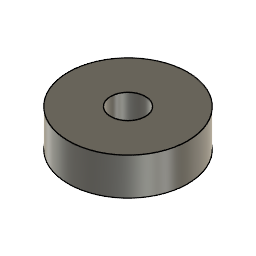
Wheel Assembly Front Side (Autodesk Fusion 360 archive; units mm, degrees)
design "Front Wheel"
Autodesk Fusion 360 part; units mm, degrees
sketch "Sketch1" plane through (0, 0, 0) normal (0, 0, 1) x (1, 0, 0)
  circle A0 centre (0, 0) radius 15.24
  circle A1 centre (0, 0) radius 4.445
  dimension "d1" = 8.89
  dimension "d2" = 30.48
  constraint coincident A0.centre A1.centre
  measures "d1" diameter of A1
  measures "d2" diameter of A0
extrude "Extrude1" add sketch "Sketch1" along normal blind 9.525
equation "d3 = ( 3 / 8 ) * 1 in"

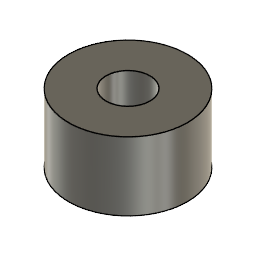
design "Shaft Collar"
Autodesk Fusion 360 part; units mm, degrees
sketch "Sketch1" plane through (0, 0, 0) normal (0, 0, 1) x (1, 0, 0)
  circle A0 centre (0, 0) radius 5.4991
  circle A1 centre (0, 0) radius 2.032
  dimension "d1" = 10.9982
  dimension "d2" = 4.064
  constraint coincident A0.centre A1.centre
  constraint concentric A0 A1
  measures "d1" diameter of A0
  measures "d2" diameter of A1
extrude "Extrude1" add sketch "Sketch1" along normal blind 6.35

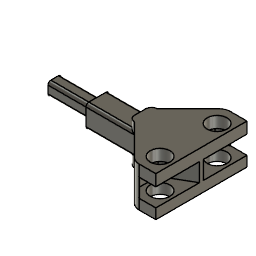
design "Wheel mount"
Autodesk Fusion 360 part; units mm, degrees
sketch "Sketch1" plane through (0, 0, 0) normal (0, 0, 1) x (1, 0, 0)
  line L0 (1.27, -2.54) -> (8.89, -2.54)
  line L1 (8.89, -2.54) -> (8.89, 2.54)
  line L2 (8.89, 2.54) -> (1.27, 2.54)
  line L3 (0, 1.27) -> (0, -1.27)
  line L4 (16.51, 10.16) -> (16.51, -10.16)
  line L5 (8.89, -10.16) -> (8.89, 10.16)
  arc A0 (1.27, 2.54) -> (0, 1.27) centre (1.27, 1.27) ccw
  arc A1 (0, -1.27) -> (1.27, -2.54) centre (1.27, -1.27) ccw
  circle A2 centre (10.795, 6.35) radius 2.2
  circle A3 centre (10.795, -6.35) radius 2.2
  line L6 (9.9421, 10.16) -> (16.51, 10.16)
  line L7 (9.9421, -10.16) -> (16.51, -10.16)
  line L8 (1.27, -2.54) -> (8.1461, -9.4161)
  line L9 (1.27, 2.54) -> (8.1461, 9.4161)
  arc A4 (9.9421, 10.16) -> (8.1461, 9.4161) centre (9.9421, 7.62) ccw
  arc A5 (8.1461, -9.4161) -> (9.9421, -10.16) centre (9.9421, -7.62) ccw
  line L10 (13.6525, 10.16) -> (13.6525, -10.16)
  dimension "d1" = 1.27
  dimension "d2" = 1.27
  dimension "d5" = 4.4
  dimension "d6" = 4.4
  dimension "d8" = 20.32
  dimension "d9" = 7.62
  dimension "d10" = 1.905
  dimension "d13" = 2.54
  dimension "d14" = 20.32
  dimension "d15" = 2.54
  dimension "d16" = 2.54
  dimension "d17" = 45
  dimension "d18" = 12.7
  dimension "d19" = 6.35
  dimension "d31" = 2.8575
  constraint horizontal L0
  constraint vertical L1
  constraint horizontal L2
  constraint vertical L3
  constraint vertical L4
  constraint vertical L5
  constraint midpoint L1 L5
  constraint tangent L2 A0
  constraint tangent L3 A0
  constraint tangent L0 A1
  constraint tangent L3 A1
  constraint midpoint origin L3
  constraint perpendicular L4 L6
  constraint coincident L5.end L9
  constraint coincident L5.end L6
  constraint tangent L9 A4
  constraint tangent L6 A4
  constraint coincident L5.start L8
  constraint coincident L5.start L7
  constraint tangent L8 A5
  constraint tangent L7 A5
  constraint vertical A2.centre A3.centre
  constraint coincident L6 L10.start
  constraint coincident L7 L10.end
  constraint perpendicular L7 L10
  measures "d1" radius of A0
  measures "d2" radius of A1
  measures "d5" diameter of A2
  measures "d6" diameter of A3
  measures "d8" distance of L4.start L4.end
  measures "d9" distance of L4 L5
  measures "d10" distance of L5 A3.centre
  measures "d13" distance of L3.start L3.end
  measures "d14" distance of L5.end L5.start
  measures "d15" radius of A4
  measures "d16" radius of A5
  measures "d17" angle of L0 L8
  measures "d18" vertical distance of A2.centre A3.centre
  measures "d19" vertical distance of origin A2.centre
  measures "d31" distance of A3.centre L10
extrude "Extrude1" add sketch "Sketch1" along normal blind 6.35 contours L0 L1 L2 L3 L5 A0 A1 | L0 L5 A3 L8 A5 | L1 L5 A2 A3 L6 L7 A4 A5 L10 | L2 L5 A2 L9 A4
sketch "Sketch3" plane through (13.6525, 0, 0) normal (1, 0, 0) x (0, 1, 0)
  line L0 (-10.16, 0) -> (10.16, 0)
  line L1 (10.16, 0) -> (10.16, 6.35)
  line L2 (10.16, 6.35) -> (-10.16, 6.35)
  line L3 (-10.16, 6.35) -> (-10.16, 0)
  line L4 (3.81, 5.08) -> (8.89, 5.08)
  line L5 (8.89, 5.08) -> (8.89, 1.27)
  line L6 (8.89, 1.27) -> (3.81, 1.27)
  line L7 (3.81, 1.27) -> (3.81, 5.08)
  line L8 (-10.16, 0) -> (10.16, 0)
  line L9 (10.16, 0) -> (10.16, 6.35)
  line L10 (10.16, 6.35) -> (-10.16, 6.35)
  line L11 (-10.16, 6.35) -> (-10.16, 0)
  line L12 (-8.89, 5.08) -> (-3.81, 5.08)
  line L13 (-3.81, 5.08) -> (-3.81, 1.27)
  line L14 (-3.81, 1.27) -> (-8.89, 1.27)
  line L15 (-8.89, 1.27) -> (-8.89, 5.08)
  dimension "d25" = 3.81
  dimension "d26" = 5.08
  dimension "d27" = 1.27
  dimension "d28" = 1.27
  dimension "d32" = 5.08
  dimension "d33" = 1.27
  dimension "d34" = 1.27
  dimension "d35" = 3.81
  constraint horizontal L4
  constraint vertical L5
  constraint horizontal L6
  constraint vertical L7
  constraint horizontal L12
  constraint vertical L13
  constraint horizontal L14
  constraint vertical L15
  measures "d25" distance of L4.end L5.end
  measures "d26" distance of L4.start L4.end
  measures "d27" distance of L1 L5
  measures "d28" distance of L0 L6
  measures "d32" distance of L12.start L12.end
  measures "d33" distance of L3 L15
  measures "d34" distance of L0 L14
  measures "d35" distance of L12.end L13.end
extrude "Extrude3" cut sketch "Sketch3" against normal blind 5.842 contours L4 L5 L6 L7 | L12 L13 L14 L15
sketch "Sketch2" plane through (0, 0, 0) normal (-1, 0, 0) x (0, -1, 0)
  line L0 (-1.27, 0) -> (1.27, 0)
  line L1 (1.27, 0) -> (1.27, 6.35)
  line L2 (1.27, 6.35) -> (-1.27, 6.35)
  line L3 (-1.27, 6.35) -> (-1.27, 0)
  line L4 (2.54, 5.715) -> (-2.54, 5.715)
  line L5 (-2.54, 5.715) -> (-2.54, 0.635)
  line L6 (-2.54, 0.635) -> (2.54, 0.635)
  line L7 (2.54, 0.635) -> (2.54, 5.715)
  line L8 (2.54, 5.715) -> (-2.54, 0.635) construction
  line L9 (-2.54, 5.715) -> (2.54, 0.635) construction
  point P0 (0, 3.175)
  dimension "d20" = 5.08
  dimension "d21" = 5.08
  dimension "d22" = 3.175
  constraint horizontal L4
  constraint perpendicular L4 L5
  constraint parallel L4 L6
  constraint parallel L5 L7
  constraint coincident L8 P0
  constraint coincident L9 P0
  constraint vertical origin P0
  measures "d20" distance of L4.end L5.end
  measures "d21" distance of L5.end L6.end
  measures "d22" vertical distance of origin P0
extrude "Extrude2" add sketch "Sketch2" along normal blind 19.05 contours L3 L4 L5 L6 | L1 L3 L4 L6 | L1 L4 L6 L7
draft "Draft1" angle 30 neutral plane through (7.8105, 0, 0) pull (1, 0, 0) 1 faces at (11.7052, -8.89, 2.54)
draft "Draft2" angle 30 neutral plane through (7.8105, 0, 0) pull (1, 0, 0) 1 faces at (11.7052, -3.81, 3.81)
draft "Draft3" angle 30 neutral plane through (7.8105, 0, 0) pull (1, 0, 0) 1 faces at (11.7052, 3.81, 2.54)
draft "Draft4" angle 30 neutral plane through (7.8105, 0, 0) pull (1, 0, 0) 1 faces at (9.7578, 8.89, 3.81)
extrude "Extrude4" add 1 faces at (3.4502, 0.4745, 6.35) along direction (0, 0, 1) blind 1.27
extrude "Extrude5" add 1 faces at (3.4502, 0.4745, 0) along direction (0, 0, -1) blind 1.27
extrude "Extrude6" cut 2 faces at (10.5895, -2.8174, 1.27) (10.5895, 2.8174, 1.27) along direction (0, 0, -1) blind 0.254
sketch "Sketch5" plane through (-19.05, 0, 0) normal (-1, 0, 0) x (0, -1, 0)
  line L0 (2.54, 0.635) -> (2.54, 5.715)
  line L1 (2.54, 5.715) -> (-2.54, 5.715)
  line L2 (-2.54, 5.715) -> (-2.54, 0.635)
  line L3 (-2.54, 0.635) -> (2.54, 0.635)
  line L4 (1.4875, 4.6625) -> (-1.4875, 4.6625)
  line L5 (-1.4875, 4.6625) -> (-1.4875, 1.6875)
  line L6 (-1.4875, 1.6875) -> (1.4875, 1.6875)
  line L7 (1.4875, 1.6875) -> (1.4875, 4.6625)
  line L8 (1.4875, 4.6625) -> (-1.4875, 1.6875) construction
  line L9 (-1.4875, 4.6625) -> (1.4875, 1.6875) construction
  point P0 (0, 3.175)
  point P1 (-10.16, -1.27)
  dimension "d50" = 2.975
  dimension "d51" = 2.975
  dimension "d52" = 4.445
  constraint horizontal L4
  constraint perpendicular L4 L5
  constraint parallel L4 L6
  constraint parallel L5 L7
  constraint coincident L8 P0
  constraint coincident L9 P0
  constraint vertical origin P0
  measures "d50" distance of L5 L7
  measures "d51" distance of L4 L6
  measures "d52" vertical distance of P0 P1
extrude "Extrude7" cut sketch "Sketch5" against normal blind 9.525
extrude "Extrude8" add 2 faces at (0, 1.6933, 2.54) (0, -1.6598, 3.81) along direction (1, 0, 0) blind 2.286
fillet "Fillet1" radius 0.635 8 edges at (-4.1275, 2.54, 5.715) (-4.1275, 2.54, 0.635) (-14.2875, 1.4875, 4.6625) (-14.2875, 1.4875, 1.6875) (-14.2875, -1.4875, 4.6625) (-14.2875, -1.4875, 1.6875) (-4.1275, -2.54, 5.715) (-4.1275, -2.54, 0.635)
equation "d10 = 0.125 in - 0.05 in"
equation "d31 = 0.165 * 0.5 in + 0.03 in"
equation "d50 = 0.125 in - 0.2 mm"
equation "d51 = 0.125 in - 0.2 mm"

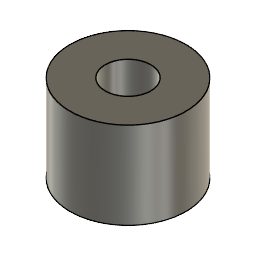
design "Front bushing"
Autodesk Fusion 360 part; units mm, degrees
sketch "Sketch1" plane through (0, 0, 0) normal (0, 0, 1) x (1, 0, 0)
  circle A0 centre (0, 0) radius 6.35
  circle A1 centre (0, 0) radius 2.4956
  dimension "d1" = 12.7
  dimension "d2" = 4.9911
  constraint coincident A0.centre A1.centre
  measures "d1" diameter of A0
  measures "d2" diameter of A1
extrude "Extrude1" add sketch "Sketch1" along normal blind 9.525
